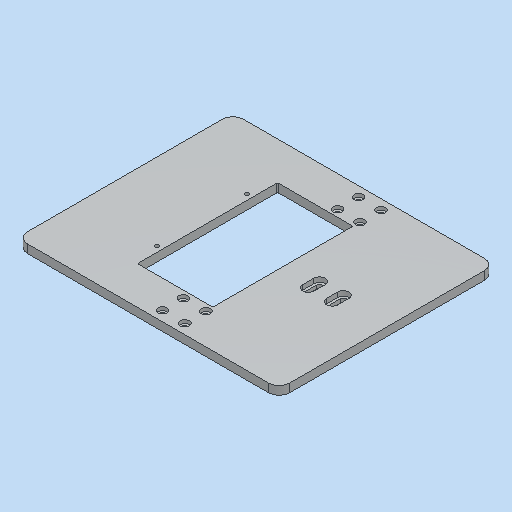
# Autodesk Inventor part: MM0948AN100_G01_108
Saved by Autodesk Inventor 2023.3 (Build 273359000, 359)
## iProperties
Part Number: MM0948AN100_G01_108
Material: 3.3547 AlMg4,5Mn0,7 - AW 5083
Description: =<RBPARTNOTITLE2>
Document SubType Name: Modeling
Designer: ric7an
Mass: 373.165 g
Surface Area: 534.533 cm^2
Volume: 138.209 cm^3
Density: 2.7 g/cm^3
Appearance: Aluminium AnP
Created: 2023-03-23
RBDOCUMENTTYPE: DRF
RBDOCUMENTVERSION: 00
RBDRAWINGMAINSCALE: 1:1
RBDRAWINGMISSINGSPEC: --
RBDRAWINGVOLUME: --
RBGBEDGESIN1: +0,5
RBGBEDGESIN2: +0,2
RBGBEDGESOUT1: -0,3
RBGBEDGESOUT2: -0,1
RBMATERIAL: =<Material>
RBMATMEETS: --
RBMATNO: =<Part Number>
RBPARTMADEOF: 6 x 154 x 187 (FM)
RBPARTNO: SIEHE MNR
RBPARTNOTITLE1: manufactured part
RBPARTNOTITLE2: Anfertigungsteil
RBPARTSAFETYINDICATOR: --
RBSURFACE: anodised colourless
RBSURFACE2: eloxiert farblos
RBZEDGESNORM: ISO13715:2002-06
RBZGENDIMCLASS: m
RBZGENDIMNORM: ISO 2768-1:1989-11
RBZGENGEOCLASS: H
RBZGENGEONORM: ISO 2768-2:1989-11
RBZSURFACENORM: ISO13D2:2002-02
RBZTOLERANCENORM: ISO 14405-1:2010-12
AnP_Material: =<Material>
AnP_TemplVers: 20190222
AnP_Kategorie: 1
MaxAbmaße: 6 x 154 x 187 (FM)
AnP_Kommentar_aktuell: =<Comments>
AnP_Material_aktuell: =<Material>
Author: FH/Wi
Keywords: =<RBPARTMADEOF>
Comments: =<RBSURFACE2>
Revision Number: 01
Autodesk Inventor part; units mm, degrees
ref_plane "YZ Plane" through (0, 0, 0) normal (1, 0, 0) x (0, 1, 0)
ref_plane "XZ Plane" through (0, 0, 0) normal (0, 1, 0) x (-1, 0, 0)
sketch "Skizze1" plane through (0, 0, 0) normal (0, 0, 1) x (1, 0, 0)
  line L0 (-93.5, 77) -> (93.5, 77)
  line L1 (93.5, 77) -> (93.5, -77)
  line L2 (93.5, -77) -> (-93.5, -77)
  line L3 (-93.5, -77) -> (-93.5, 77)
  line L4 (-130.9, 0) -> (130.9, 0) projected
  line L5 (0, 107.8) -> (0, -107.8) projected
  line L6 (-34.6, 50) -> (19.2, 50)
  line L7 (19.2, 50) -> (19.2, -50)
  line L8 (19.2, -50) -> (-34.6, -50)
  line L9 (-34.6, -50) -> (-34.6, 50)
  dimension "d0" = 187
  dimension "d1" = 154
  dimension "d5" = 100
  dimension "d6" = 53.8
  dimension "d34" = 74.3
  constraints: 16 end point, 4 parallel, 2 horizontal, 2 perpendicular, 3 other
  measures "d0" distance of L0.start L0.end
  measures "d1" distance of L0.end L1.end
  measures "d5" distance of L6.end L7.end
  measures "d6" distance of L6.start L6.end
  measures "d34" distance between parallel lines of L1 L7
extrude "Extrusion1" add sketch "Skizze1" along normal blind 6 contours L0 L5 L6 L9 L4 L3 | L0 L1 L4 L7 L6 L5 | L4 L9 L8 L5 L2 L3 | L1 L2 L5 L8 L7 L4
sketch "Skizze4" plane through (0, 0, 0) normal (0, 0, -1) x (-1, 0, 0)
  line L0 (0, -107.8) -> (0, 107.8) projected
  line L1 (-130.9, 0) -> (130.9, 0) projected
  line L2 (34.6, -50) -> (-19.2, -50) projected
  line L3 (34.6, 50) -> (34.6, -50) projected
  line L4 (-19.2, -50) -> (-19.2, 50) projected
  point P0 (0, 0)
  point P1 (38.5, 32)
  point P2 (38.5, -32)
  dimension "d32" = 64
  dimension "d53" = 57.7
  constraints: 1 symmetric about line, 1 vertical alignment
  measures "d32" distance of point (38.5, -32) point (38.5, 32)
  measures "d53" distance from line of point (38.5, 32) L4
hole "Bohrung2" at (-38.5, -32, 0) at (-38.5, 32, 0) direction (0, 0, 1) diameter 2.7 end through all
sketch "Skizze7" plane through (0, 0, 6) normal (0, 0, 1) x (1, 0, 0)
  line L0 (0, 107.8) -> (0, -107.8) projected
  line L1 (-130.9, 0) -> (130.9, 0) projected
  line L2 (19.2, 50) -> (19.2, -50) projected
  line L3 (93.5, -77) -> (93.5, 77) projected
  point P0 (0, 0)
  point P1 (41.35, 0)
  point P2 (58.35, 0)
  dimension "d57" = 17
  dimension "d67" = 52.15
  constraints: 2 point on line
  measures "d57" distance of point (58.35, 0) point (41.35, 0)
  measures "d67" distance from line of L3 point (41.35, 0)
hole "Bohrung5" at (41.35, 0, 6) at (58.35, 0, 6) direction (0, 0, -1) diameter 4.5 end through all counterbore diameter 8 counterbore depth 3.4 clearance for "Flachk.Schr. DIN 6912  versenkt" size "M4" standard "ISO"
sketch "Skizze8" plane through (0, 0, 6) normal (0, 0, 1) x (1, 0, 0)
  line L0 (93.5, -77) -> (93.5, 77) projected
  line L1 (0, 107.8) -> (0, -107.8) projected
  line L2 (-130.9, 0) -> (130.9, 0) projected
  point P0 (0, 0)
  point P1 (3.2, 55)
  point P2 (3.2, 70)
  point P3 (19.2, 70)
  point P4 (19.2, 55)
  point P5 (3.2, -70)
  point P6 (3.2, -55)
  point P7 (19.2, -55)
  point P8 (19.2, -70)
  dimension "d68" = 16
  dimension "d69" = 15
  dimension "d70" = 15
  dimension "d71" = 16
  dimension "d72" = 74.3
  dimension "d73" = 55
  dimension "d74" = 55
  constraints: 5 vertical alignment, 4 horizontal alignment
  measures "d68" distance of point (19.2, -70) point (3.2, -70)
  measures "d69" distance of point (3.2, -55) point (3.2, -70)
  measures "d70" distance of point (3.2, 70) point (3.2, 55)
  measures "d71" distance of point (19.2, 70) point (3.2, 70)
  measures "d72" distance from line of L0 point (19.2, -70)
  measures "d73" distance from line of point (19.2, 55) L2
  measures "d74" distance from line of L2 point (19.2, -55)
hole "Bohrung6" at (3.2, 55, 6) at (3.2, 70, 6) at (19.2, 70, 6) at (19.2, 55, 6) at (3.2, -70, 6) at (3.2, -55, 6) at (19.2, -55, 6) at (19.2, -70, 6) direction (0, 0, -1) diameter 3.4 end through all counterbore diameter 6.5 counterbore depth 2.4 clearance for "Flachk.Schr. DIN 6912  versenkt" size "M3" standard "ISO"
sketch "Skizze9" plane through (0, 0, 6) normal (0, 0, 1) x (1, 0, 0)
  line L0 (93.5, 77) -> (93.5, -77) projected
  line L1 (93.5, -77) -> (93.5, 77) projected
  line L2 (-130.9, 0) -> (130.9, 0) projected
  line L3 (41.35, 4) -> (41.35, -4) construction
  line L4 (37.35, 4) -> (37.35, -4)
  line L5 (45.35, -4) -> (45.35, 4)
  arc A0 (45.35, 4) -> (37.35, 4) centre (41.35, 4) ccw
  arc A1 (37.35, -4) -> (45.35, -4) centre (41.35, -4) ccw
  line L6 (58.35, 4) -> (58.35, -4) construction
  line L7 (54.35, 4) -> (54.35, -4)
  line L8 (62.35, -4) -> (62.35, 4)
  arc A2 (62.35, 4) -> (54.35, 4) centre (58.35, 4) ccw
  arc A3 (54.35, -4) -> (62.35, -4) centre (58.35, -4) ccw
  circle A4 centre (41.35, 0) radius 2.25 construction
  circle A5 centre (58.35, 0) radius 4 construction
  point P0 (0, 0)
  dimension "d91" = 8
  dimension "d92" = 8
  dimension "d93" = 8
  dimension "d94" = 8
  constraints: 16 end point, 8 point on circle, 8 tangent, 4 centre point, 3 parallel, 2 coincident, 2 midpoint, 2 point on line, 1 vertical, 1 other
  measures "d91" distance of L3.start L3.end
  measures "d92" distance of L6.start L6.end
  measures "d93" distance between parallel lines of L5 L4
  measures "d94" distance between parallel lines of L8 L7
extrude "Extrusion3" cut sketch "Skizze9" against normal blind 3.4
sketch "Skizze10" plane through (28.35, -44, 2.6) normal (0, 0, 1) x (1, 0, 0)
  line L0 (26, 40) -> (26, 48) projected
  arc A0 (34, 48) -> (26, 48) centre (30, 48) ccw projected
  line L1 (34, 48) -> (34, 40) projected
  arc A1 (26, 40) -> (34, 40) centre (30, 40) ccw projected
  arc A2 (17, 48) -> (9, 48) centre (13, 48) ccw projected
  line L2 (17, 48) -> (17, 40) projected
  arc A3 (9, 40) -> (17, 40) centre (13, 40) ccw projected
  circle A4 centre (-9.15, -11) radius 3.25 projected
  circle A5 centre (-25.15, -26) radius 3.25 projected
  circle A6 centre (-9.15, 114) radius 3.25 projected
  circle A7 centre (-25.15, 99) radius 3.25 projected
  circle A8 centre (-25.15, 114) radius 3.25 projected
  circle A9 centre (-9.15, 99) radius 3.25 projected
  circle A10 centre (-25.15, -11) radius 3.25 projected
  circle A11 centre (-9.15, -26) radius 3.25 projected
  circle A12 centre (-66.85, 12) radius 1.35 projected
  circle A13 centre (-66.85, 76) radius 1.35 projected
  line L3 (-9.15, 94) -> (-9.15, -6) projected
  line L4 (-9.15, -6) -> (-62.95, -6) projected
  line L5 (-62.95, -6) -> (-62.95, 94) projected
  line L6 (-62.95, 94) -> (-9.15, 94) projected
  line L7 (65.15, 121) -> (-121.85, 121) projected
  line L8 (-121.85, 121) -> (-121.85, -33) projected
  line L9 (-121.85, -33) -> (65.15, -33) projected
  line L10 (65.15, -33) -> (65.15, 121) projected
  line L11 (10.75, 48) -> (10.75, 40)
  arc A14 (10.75, 40) -> (15.25, 40) centre (13, 40) ccw
  line L12 (15.25, 40) -> (15.25, 48)
  arc A15 (15.25, 48) -> (10.75, 48) centre (13, 48) ccw
  line L13 (27.75, 48) -> (27.75, 40)
  arc A16 (27.75, 40) -> (32.25, 40) centre (30, 40) ccw
  line L14 (32.25, 40) -> (32.25, 48)
  arc A17 (32.25, 48) -> (27.75, 48) centre (30, 48) ccw
  line L15 (9, 40) -> (9, 48) projected
  point P0 (-28.35, 44)
  dimension "d98" = 4.5
  dimension "d99" = 4.5
  constraints: 8 end point, 8 point on circle, 4 centre point, 5 other
  measures "d98" distance between parallel lines of L12 L11
  measures "d99" distance between parallel lines of L14 L13
extrude "Extrusion4" cut sketch "Skizze10" against normal blind 10 contours A15 L12 A14 L11 | A17 L14 A16 L13
fillet "Rundung1" radius 1 4 edges at (-34.6, -50, 3) (19.2, -50, 3) (19.2, 50, 3) (-34.6, 50, 3)
fillet "Rundung2" radius 7.5 4 edges at (-93.5, -77, 3) (-93.5, 77, 3) (93.5, 77, 3) (93.5, -77, 3)
ref_plane "Ebene_Langloch_Mitte" through (41.35, -69.5, 0) normal (1, 0, 0) x (0, 0, -1)
equation "\"d70\" = d69"
equation "\"d71\" = d68"
equation "\"d103\" = -d67"
